Feet (Autodesk Fusion 360 design; units mm, degrees)
Autodesk Fusion 360 part; units mm, degrees
sketch "Sketch1" plane through (0, 0, 0) normal (0, 1, 0) x (1, 0, 0)
  circle A0 centre (0, 0) radius 120
  dimension "d1" = 240
  constraint coincident A0.centre origin
  measures "d1" diameter of A0
extrude "Extrude1" add sketch "Sketch1" along normal blind 6.1 makes body 1
sketch "Sketch2" plane through (0, 6.1, 0) normal (0, 1, 0) x (-1, 0, 0)
  circle A0 centre (0, 0) radius 120
  line L0 (0, 0) -> (0, 120)
  line L1 (0, 0) -> (-120, 0)
  line L2 (0, 0) -> (0, -120)
  line L3 (0, 0) -> (120, 0)
  line L4 (41.7567, 102.5006) -> (41.7567, 134.5006)
  line L5 (41.7567, 134.5006) -> (19.7567, 134.5006)
  line L6 (19.7567, 102.5006) -> (19.7567, 134.5006)
  line L7 (41.7567, 102.5006) -> (19.7567, 102.5006)
  dimension "d6" = 120
  dimension "d7" = 120
  dimension "d8" = 120
  dimension "d9" = 120
  constraint coincident A0.centre L0.start
  constraint vertical L0
  constraint perpendicular L0 L1
  constraint perpendicular L1 L2
  constraint perpendicular L2 L3
  constraint perpendicular L5 L6
  constraint perpendicular L6 L7
  measures "d6" distance of A0.centre L0.end
  measures "d7" distance of A0.centre L1.end
  measures "d8" distance of A0.centre L2.end
  measures "d9" distance of A0.centre L3.end
extrude "Extrude2" add sketch "Sketch2" along normal blind 3 separate body contours A0 L4 L5 L6 | A0 L4 L6 L7 makes body 2
sketch "Sketch3" plane through (0, 6.1, 0) normal (0, -1, 0) x (1, 0, 0)
  line L0 (-19.7567, 134.5006) -> (-41.7567, 134.5006)
  line L1 (-41.7567, 134.5006) -> (-41.7567, 102.5006)
  line L2 (-41.7567, 102.5006) -> (-19.7567, 102.5006)
  line L3 (-19.7567, 102.5006) -> (-19.7567, 134.5006)
  arc A0 (-19.7567, 118.3625) -> (-41.7567, 112.5006) centre (0, 0) ccw
  circle A1 centre (0, 0) radius 120
  constraint coincident L3 A0.start
  constraint coincident A0.start A1
  constraint coincident L1 A0.end
  constraint coincident A0.end A1
extrude "Extrude3" add sketch "Sketch3" along normal blind 9 separate body contours L0 L1 L3 A0 A1 makes body 3
combine "Combine1" operation add target body 2 tool bodies 3
sketch "Sketch4" plane through (0, -2.9, 0) normal (0, -1, 0) x (1, 0, 0)
  line L0 (-19.7567, 118.3625) -> (-19.7567, 134.5006)
  line L1 (-19.7567, 134.5006) -> (-41.7567, 134.5006)
  line L2 (-41.7567, 134.5006) -> (-41.7567, 112.5006)
  arc A0 (-19.7567, 118.3625) -> (-41.7567, 112.5006) centre (0, 0) ccw
  line L3 (-41.7567, 112.5006) -> (-41.7567, 111.5006)
  line L4 (-19.7567, 118.3625) -> (-19.7567, 117.3625)
  line L5 (-30.896, 115.9545) -> (-30.896, 114.9545)
  arc A1 (-19.7567, 117.3625) -> (-41.7567, 111.5006) centre (0, -1) ccw
  dimension "d18" = 1
  dimension "d19" = 1
  dimension "d20" = 1
  constraint coincident L2.end A0.end
  constraint parallel L2 L3
  constraint coincident L0.start A0.start
  constraint parallel L0 L4
  constraint midpoint A0 L5.start
  constraint vertical L5
  constraint coincident L5.end A1
  measures "d18" distance of L2.end L3.end
  measures "d19" distance of L0.start L4.end
  measures "d20" distance of L5.start L5.end
extrude "Extrude4" add sketch "Sketch4" against normal blind 2.85 contours A0 L4 L5 A1 | A0 L3 L5 A1 bodies 2
sketch "Sketch5" plane through (0, -2.9, 0) normal (0, -1, 0) x (1, 0, 0)
  line L0 (-19.7567, 117.3625) -> (-19.7567, 134.5006)
  line L1 (-19.7567, 134.5006) -> (-41.7567, 134.5006)
  line L2 (-41.7567, 134.5006) -> (-41.7567, 111.5006)
  arc A0 (-19.7567, 117.3625) -> (-41.7567, 111.5006) centre (0, -1) ccw
extrude "Extrude5" add sketch "Sketch5" along normal blind 1 bodies 2
sketch "Sketch6" plane through (0, -3.9, 0) normal (0, -1, 0) x (1, 0, 0)
  line L0 (-19.7567, 134.5006) -> (-41.7567, 134.5006)
  line L1 (-41.7567, 134.5006) -> (-41.7567, 111.5006)
  arc A0 (-19.7567, 117.3625) -> (-41.7567, 111.5006) centre (0, -1) ccw
  line L2 (-19.7567, 117.3625) -> (-19.7567, 134.5006)
  line L3 (-30.7567, 134.5006) -> (-30.7567, 127.5006)
  circle A1 centre (-30.7567, 127.5006) radius 4
  dimension "d26" = 8
  constraint midpoint L0 L3.start
  constraint perpendicular L0 L3
  constraint coincident L3.end A1.centre
  measures "d26" diameter of A1
extrude "Extrude6" cut sketch "Sketch6" against normal blind 8 contours A1 bodies 2
sketch "Sketch7" plane through (0, 4.1, 0) normal (0, -1, 0) x (1, 0, 0)
  circle A0 centre (-30.7567, 127.5006) radius 4
  circle A1 centre (-30.7567, 127.5006) radius 2.125
  dimension "d29" = 4.25
  constraint concentric A0 A1
  measures "d29" diameter of A1
extrude "Extrude7" cut sketch "Sketch7" against normal blind 5 contours A1 bodies 2
fillet "Fillet1" radius 2.1 2 edges at (-30.896, -0.05, 114.9545) (-30.896, -3.9, 114.9545) on bodies 2
fillet "Fillet2" radius 0.5 2 edges at (-19.7567, 2.6, 134.5006) (-41.7567, 2.6, 134.5006) on bodies 2
fillet "Fillet3" radius 2 2 edges at (-30.7567, 9.1, 102.5006) (-30.7567, 6.1, 102.5006) on bodies 2
mirror "Mirror1" about plane through (0, 0, 0) normal (1, 0, 0) of bodies 2 makes body 4
hidden bodies 1
